Autodesk Fusion 360 part; units mm, degrees
(part 8 of 8)
equation "d1576 = ( ( ( 115 mm ) - holderFrameX / 2 ) + ( holderFrameX / 2 - holderWidth / 2 + holderHookOverlap ) ) - ( ( 115 mm ) - holderFrameX / 2 )"
equation "d1577 = ( ( ( ( ( keyRowOne ) + holderSpringY ) - holderSpringWidth / 2 ) + faceOriginV ) + ( holderSpringWidth ) ) - ( ( ( ( keyRowOne ) + holderSpringY ) - holderSpringWidth / 2 ) + faceOriginV )"
equation "d1578 = -( holderHookThickness )"
equation "d1581 = ( 115 mm ) + holderWidth / 2 + holderFit"
equation "d1582 = ( ( ( keyRowOne ) + holderSpringY ) - holderSpringWidth / 2 - 0.6 mm ) + faceOriginV"
equation "d1583 = ( ( ( 115 mm ) + holderWidth / 2 + holderFit ) + ( holderFrameX / 2 - holderWidth / 2 - holderFit + 0.1 mm ) ) - ( ( 115 mm ) + holderWidth / 2 + holderFit )"
equation "d1584 = ( ( ( ( ( keyRowOne ) + holderSpringY ) - holderSpringWidth / 2 - 0.6 mm ) + faceOriginV ) + ( 0.6 mm ) ) - ( ( ( ( keyRowOne ) + holderSpringY ) - holderSpringWidth / 2 - 0.6 mm ) + faceOriginV )"
equation "d1585 = -( holderBottomDepth + holderHookThickness - shellWall - carrierClearance - carrierThickness - 1 mm + 0.2 mm )"
equation "d1587 = ( 115 mm ) + holderWidth / 2 + holderFit"
equation "d1588 = ( ( ( keyRowOne ) + holderSpringY ) + holderSpringWidth / 2 ) + faceOriginV"
equation "d1589 = ( ( ( 115 mm ) + holderWidth / 2 + holderFit ) + ( holderFrameX / 2 - holderWidth / 2 - holderFit + 0.1 mm ) ) - ( ( 115 mm ) + holderWidth / 2 + holderFit )"
equation "d1590 = ( ( ( ( ( keyRowOne ) + holderSpringY ) + holderSpringWidth / 2 ) + faceOriginV ) + ( 0.6 mm ) ) - ( ( ( ( keyRowOne ) + holderSpringY ) + holderSpringWidth / 2 ) + faceOriginV )"
equation "d1591 = -( holderBottomDepth + holderHookThickness - shellWall - carrierClearance - carrierThickness - 1 mm + 0.2 mm )"
equation "d1593 = ( 115 mm ) + holderWidth / 2 + holderFit"
equation "d1594 = ( ( ( keyRowOne ) + holderSpringY ) - holderSpringWidth / 2 ) + faceOriginV"
equation "d1595 = ( ( ( 115 mm ) + holderWidth / 2 + holderFit ) + ( holderFrameX / 2 - 0.8 mm - holderWidth / 2 - holderFit ) ) - ( ( 115 mm ) + holderWidth / 2 + holderFit )"
equation "d1596 = ( ( ( ( ( keyRowOne ) + holderSpringY ) - holderSpringWidth / 2 ) + faceOriginV ) + ( holderSpringWidth ) ) - ( ( ( ( keyRowOne ) + holderSpringY ) - holderSpringWidth / 2 ) + faceOriginV )"
equation "d1597 = -( holderHeight + holderHookThickness + 0.2 mm )"
equation "d1599 = ( 115 mm ) + holderWidth / 2 - holderHookOverlap"
equation "d1600 = ( ( ( keyRowOne ) + holderSpringY ) - holderSpringWidth / 2 ) + faceOriginV"
equation "d1601 = ( ( ( 115 mm ) + holderWidth / 2 - holderHookOverlap ) + ( holderFrameX / 2 - holderWidth / 2 + holderHookOverlap ) ) - ( ( 115 mm ) + holderWidth / 2 - holderHookOverlap )"
equation "d1602 = ( ( ( ( ( keyRowOne ) + holderSpringY ) - holderSpringWidth / 2 ) + faceOriginV ) + ( holderSpringWidth ) ) - ( ( ( ( keyRowOne ) + holderSpringY ) - holderSpringWidth / 2 ) + faceOriginV )"
equation "d1603 = -( holderHookThickness )"
equation "d1606 = ( 115 mm ) - 11 mm"
equation "d1607 = ( ( keyRowOne ) * cos(caseTilt) + ( holderBottomDepth + holderLidGap ) * sin(caseTilt) ) - 11 mm"
equation "d1608 = ( ( ( 115 mm ) - 11 mm ) + ( 22 mm ) ) - ( ( 115 mm ) - 11 mm )"
equation "d1609 = ( ( ( ( keyRowOne ) * cos(caseTilt) + ( holderBottomDepth + holderLidGap ) * sin(caseTilt) ) - 11 mm ) + ( 22 mm ) ) - ( ( ( keyRowOne ) * cos(caseTilt) + ( holderBottomDepth + holderLidGap ) * sin(caseTilt) ) - 11 mm )"
equation "d1610 = bottomThickness"
equation "d1612 = ( 115 mm ) + ( -2.5 mm ) - 1.2 mm"
equation "d1613 = ( ( ( keyRowOne ) - 1.2 mm ) * cos(caseTilt) + ( holderBottomDepth + holderLidGap ) * sin(caseTilt) ) - 2.5 mm"
equation "d1614 = ( ( ( 115 mm ) + ( -2.5 mm ) - 1.2 mm ) + ( 2.4 mm ) ) - ( ( 115 mm ) + ( -2.5 mm ) - 1.2 mm )"
equation "d1615 = ( ( ( ( ( keyRowOne ) - 1.2 mm ) * cos(caseTilt) + ( holderBottomDepth + holderLidGap ) * sin(caseTilt) ) - 2.5 mm ) + ( 5 mm ) ) - ( ( ( ( keyRowOne ) - 1.2 mm ) * cos(caseTilt) + ( holderBottomDepth + holderLidGap ) * sin(caseTilt) ) - 2.5 mm )"
equation "d1616 = ( frontHeight + ( ( keyRowOne ) - 1.2 mm ) * sin(caseTilt) - ( holderBottomDepth + holderLidGap ) * cos(caseTilt) ) - bottomThickness - 2 mm"
equation "d1618 = ( 115 mm ) + ( -2.5 mm ) - 0.5 mm"
equation "d1619 = ( ( ( keyRowOne ) - 1.2 mm ) * cos(caseTilt) + ( holderBottomDepth + holderLidGap ) * sin(caseTilt) ) - 1.5 mm"
equation "d1620 = ( ( ( 115 mm ) + ( -2.5 mm ) - 0.5 mm ) + ( 1 mm ) ) - ( ( 115 mm ) + ( -2.5 mm ) - 0.5 mm )"
equation "d1621 = ( ( ( ( ( keyRowOne ) - 1.2 mm ) * cos(caseTilt) + ( holderBottomDepth + holderLidGap ) * sin(caseTilt) ) - 1.5 mm ) + ( 3 mm ) ) - ( ( ( ( keyRowOne ) - 1.2 mm ) * cos(caseTilt) + ( holderBottomDepth + holderLidGap ) * sin(caseTilt) ) - 1.5 mm )"
equation "d1622 = ( frontHeight + ( ( keyRowOne ) - 1.2 mm ) * sin(caseTilt) - ( holderBottomDepth + holderLidGap ) * cos(caseTilt) ) - bottomThickness + 0.5 mm"
equation "d1624 = ( ( 115 mm ) + ( -2.5 mm ) - 0.5 mm ) - 0.1 mm"
equation "d1625 = ( ( ( keyRowOne ) - 1.2 mm ) - 2 mm ) + faceOriginV"
equation "d1626 = ( ( ( ( 115 mm ) + ( -2.5 mm ) - 0.5 mm ) - 0.1 mm ) + ( 1.2 mm ) ) - ( ( ( 115 mm ) + ( -2.5 mm ) - 0.5 mm ) - 0.1 mm )"
equation "d1627 = ( ( ( ( ( keyRowOne ) - 1.2 mm ) - 2 mm ) + faceOriginV ) + ( 4 mm ) ) - ( ( ( ( keyRowOne ) - 1.2 mm ) - 2 mm ) + faceOriginV )"
equation "d1628 = rearHeight"
equation "d1630 = ( 115 mm ) + ( 2.5 mm ) - 1.2 mm"
equation "d1631 = ( ( ( keyRowOne ) - 1.2 mm ) * cos(caseTilt) + ( holderBottomDepth + holderLidGap ) * sin(caseTilt) ) - 2.5 mm"
equation "d1632 = ( ( ( 115 mm ) + ( 2.5 mm ) - 1.2 mm ) + ( 2.4 mm ) ) - ( ( 115 mm ) + ( 2.5 mm ) - 1.2 mm )"
equation "d1633 = ( ( ( ( ( keyRowOne ) - 1.2 mm ) * cos(caseTilt) + ( holderBottomDepth + holderLidGap ) * sin(caseTilt) ) - 2.5 mm ) + ( 5 mm ) ) - ( ( ( ( keyRowOne ) - 1.2 mm ) * cos(caseTilt) + ( holderBottomDepth + holderLidGap ) * sin(caseTilt) ) - 2.5 mm )"
equation "d1634 = ( frontHeight + ( ( keyRowOne ) - 1.2 mm ) * sin(caseTilt) - ( holderBottomDepth + holderLidGap ) * cos(caseTilt) ) - bottomThickness - 2 mm"
equation "d1636 = ( 115 mm ) + ( 2.5 mm ) - 0.5 mm"
equation "d1637 = ( ( ( keyRowOne ) - 1.2 mm ) * cos(caseTilt) + ( holderBottomDepth + holderLidGap ) * sin(caseTilt) ) - 1.5 mm"
equation "d1638 = ( ( ( 115 mm ) + ( 2.5 mm ) - 0.5 mm ) + ( 1 mm ) ) - ( ( 115 mm ) + ( 2.5 mm ) - 0.5 mm )"
equation "d1639 = ( ( ( ( ( keyRowOne ) - 1.2 mm ) * cos(caseTilt) + ( holderBottomDepth + holderLidGap ) * sin(caseTilt) ) - 1.5 mm ) + ( 3 mm ) ) - ( ( ( ( keyRowOne ) - 1.2 mm ) * cos(caseTilt) + ( holderBottomDepth + holderLidGap ) * sin(caseTilt) ) - 1.5 mm )"
equation "d1640 = ( frontHeight + ( ( keyRowOne ) - 1.2 mm ) * sin(caseTilt) - ( holderBottomDepth + holderLidGap ) * cos(caseTilt) ) - bottomThickness + 0.5 mm"
equation "d1642 = ( ( 115 mm ) + ( 2.5 mm ) - 0.5 mm ) - 0.1 mm"
equation "d1643 = ( ( ( keyRowOne ) - 1.2 mm ) - 2 mm ) + faceOriginV"
equation "d1644 = ( ( ( ( 115 mm ) + ( 2.5 mm ) - 0.5 mm ) - 0.1 mm ) + ( 1.2 mm ) ) - ( ( ( 115 mm ) + ( 2.5 mm ) - 0.5 mm ) - 0.1 mm )"
equation "d1645 = ( ( ( ( ( keyRowOne ) - 1.2 mm ) - 2 mm ) + faceOriginV ) + ( 4 mm ) ) - ( ( ( ( keyRowOne ) - 1.2 mm ) - 2 mm ) + faceOriginV )"
equation "d1646 = rearHeight"
equation "d1648 = ( layoutGap + keycapSize / 2 + 0 * keyPitch ) + ( -3 mm ) - 0.5 mm"
equation "d1649 = ( ( keyRowOne ) + 4 mm ) + faceOriginV"
equation "d1650 = ( ( ( layoutGap + keycapSize / 2 + 0 * keyPitch ) + ( -3 mm ) - 0.5 mm ) + ( 1 mm ) ) - ( ( layoutGap + keycapSize / 2 + 0 * keyPitch ) + ( -3 mm ) - 0.5 mm )"
equation "d1651 = ( ( ( ( keyRowOne ) + 4 mm ) + faceOriginV ) + ( holderFrameY / 2 - 4 mm ) ) - ( ( ( keyRowOne ) + 4 mm ) + faceOriginV )"
equation "d1654 = ( layoutGap + keycapSize / 2 + 0 * keyPitch ) + ( 3 mm ) - 0.5 mm"
equation "d1655 = ( ( keyRowOne ) + 4 mm ) + faceOriginV"
equation "d1656 = ( ( ( layoutGap + keycapSize / 2 + 0 * keyPitch ) + ( 3 mm ) - 0.5 mm ) + ( 1 mm ) ) - ( ( layoutGap + keycapSize / 2 + 0 * keyPitch ) + ( 3 mm ) - 0.5 mm )"
equation "d1657 = ( ( ( ( keyRowOne ) + 4 mm ) + faceOriginV ) + ( holderFrameY / 2 - 4 mm ) ) - ( ( ( keyRowOne ) + 4 mm ) + faceOriginV )"
equation "d1660 = ( layoutGap + keycapSize / 2 + 1 * keyPitch ) + ( -3 mm ) - 0.5 mm"
equation "d1661 = ( ( keyRowOne ) + 4 mm ) + faceOriginV"
equation "d1662 = ( ( ( layoutGap + keycapSize / 2 + 1 * keyPitch ) + ( -3 mm ) - 0.5 mm ) + ( 1 mm ) ) - ( ( layoutGap + keycapSize / 2 + 1 * keyPitch ) + ( -3 mm ) - 0.5 mm )"
equation "d1663 = ( ( ( ( keyRowOne ) + 4 mm ) + faceOriginV ) + ( holderFrameY / 2 - 4 mm ) ) - ( ( ( keyRowOne ) + 4 mm ) + faceOriginV )"
equation "d1666 = ( layoutGap + keycapSize / 2 + 1 * keyPitch ) + ( 3 mm ) - 0.5 mm"
equation "d1667 = ( ( keyRowOne ) + 4 mm ) + faceOriginV"
equation "d1668 = ( ( ( layoutGap + keycapSize / 2 + 1 * keyPitch ) + ( 3 mm ) - 0.5 mm ) + ( 1 mm ) ) - ( ( layoutGap + keycapSize / 2 + 1 * keyPitch ) + ( 3 mm ) - 0.5 mm )"
equation "d1669 = ( ( ( ( keyRowOne ) + 4 mm ) + faceOriginV ) + ( holderFrameY / 2 - 4 mm ) ) - ( ( ( keyRowOne ) + 4 mm ) + faceOriginV )"
equation "d1672 = ( layoutGap + keycapSize / 2 + 2 * keyPitch ) + ( -3 mm ) - 0.5 mm"
equation "d1673 = ( ( keyRowOne ) + 4 mm ) + faceOriginV"
equation "d1674 = ( ( ( layoutGap + keycapSize / 2 + 2 * keyPitch ) + ( -3 mm ) - 0.5 mm ) + ( 1 mm ) ) - ( ( layoutGap + keycapSize / 2 + 2 * keyPitch ) + ( -3 mm ) - 0.5 mm )"
equation "d1675 = ( ( ( ( keyRowOne ) + 4 mm ) + faceOriginV ) + ( holderFrameY / 2 - 4 mm ) ) - ( ( ( keyRowOne ) + 4 mm ) + faceOriginV )"
equation "d1678 = ( layoutGap + keycapSize / 2 + 2 * keyPitch ) + ( 3 mm ) - 0.5 mm"
equation "d1679 = ( ( keyRowOne ) + 4 mm ) + faceOriginV"
equation "d1680 = ( ( ( layoutGap + keycapSize / 2 + 2 * keyPitch ) + ( 3 mm ) - 0.5 mm ) + ( 1 mm ) ) - ( ( layoutGap + keycapSize / 2 + 2 * keyPitch ) + ( 3 mm ) - 0.5 mm )"
equation "d1681 = ( ( ( ( keyRowOne ) + 4 mm ) + faceOriginV ) + ( holderFrameY / 2 - 4 mm ) ) - ( ( ( keyRowOne ) + 4 mm ) + faceOriginV )"
equation "d1684 = ( layoutGap + keycapSize / 2 + 0 * keyPitch ) + ( -3 mm ) - 0.5 mm"
equation "d1685 = ( ( keyRowTwo ) + 4 mm ) + faceOriginV"
equation "d1686 = ( ( ( layoutGap + keycapSize / 2 + 0 * keyPitch ) + ( -3 mm ) - 0.5 mm ) + ( 1 mm ) ) - ( ( layoutGap + keycapSize / 2 + 0 * keyPitch ) + ( -3 mm ) - 0.5 mm )"
equation "d1687 = ( ( ( ( keyRowTwo ) + 4 mm ) + faceOriginV ) + ( holderFrameY / 2 - 4 mm ) ) - ( ( ( keyRowTwo ) + 4 mm ) + faceOriginV )"
equation "d1690 = ( layoutGap + keycapSize / 2 + 0 * keyPitch ) + ( 3 mm ) - 0.5 mm"
equation "d1691 = ( ( keyRowTwo ) + 4 mm ) + faceOriginV"
equation "d1692 = ( ( ( layoutGap + keycapSize / 2 + 0 * keyPitch ) + ( 3 mm ) - 0.5 mm ) + ( 1 mm ) ) - ( ( layoutGap + keycapSize / 2 + 0 * keyPitch ) + ( 3 mm ) - 0.5 mm )"
equation "d1693 = ( ( ( ( keyRowTwo ) + 4 mm ) + faceOriginV ) + ( holderFrameY / 2 - 4 mm ) ) - ( ( ( keyRowTwo ) + 4 mm ) + faceOriginV )"
equation "d1696 = ( layoutGap + keycapSize / 2 + 1 * keyPitch ) + ( -3 mm ) - 0.5 mm"
equation "d1697 = ( ( keyRowTwo ) + 4 mm ) + faceOriginV"
equation "d1698 = ( ( ( layoutGap + keycapSize / 2 + 1 * keyPitch ) + ( -3 mm ) - 0.5 mm ) + ( 1 mm ) ) - ( ( layoutGap + keycapSize / 2 + 1 * keyPitch ) + ( -3 mm ) - 0.5 mm )"
equation "d1699 = ( ( ( ( keyRowTwo ) + 4 mm ) + faceOriginV ) + ( holderFrameY / 2 - 4 mm ) ) - ( ( ( keyRowTwo ) + 4 mm ) + faceOriginV )"
equation "d1702 = ( layoutGap + keycapSize / 2 + 1 * keyPitch ) + ( 3 mm ) - 0.5 mm"
equation "d1703 = ( ( keyRowTwo ) + 4 mm ) + faceOriginV"
equation "d1704 = ( ( ( layoutGap + keycapSize / 2 + 1 * keyPitch ) + ( 3 mm ) - 0.5 mm ) + ( 1 mm ) ) - ( ( layoutGap + keycapSize / 2 + 1 * keyPitch ) + ( 3 mm ) - 0.5 mm )"
equation "d1705 = ( ( ( ( keyRowTwo ) + 4 mm ) + faceOriginV ) + ( holderFrameY / 2 - 4 mm ) ) - ( ( ( keyRowTwo ) + 4 mm ) + faceOriginV )"
equation "d1708 = ( layoutGap + keycapSize / 2 + 2 * keyPitch ) + ( -3 mm ) - 0.5 mm"
equation "d1709 = ( ( keyRowTwo ) + 4 mm ) + faceOriginV"
equation "d1710 = ( ( ( layoutGap + keycapSize / 2 + 2 * keyPitch ) + ( -3 mm ) - 0.5 mm ) + ( 1 mm ) ) - ( ( layoutGap + keycapSize / 2 + 2 * keyPitch ) + ( -3 mm ) - 0.5 mm )"
equation "d1711 = ( ( ( ( keyRowTwo ) + 4 mm ) + faceOriginV ) + ( holderFrameY / 2 - 4 mm ) ) - ( ( ( keyRowTwo ) + 4 mm ) + faceOriginV )"
equation "d1714 = ( layoutGap + keycapSize / 2 + 2 * keyPitch ) + ( 3 mm ) - 0.5 mm"
equation "d1715 = ( ( keyRowTwo ) + 4 mm ) + faceOriginV"
equation "d1716 = ( ( ( layoutGap + keycapSize / 2 + 2 * keyPitch ) + ( 3 mm ) - 0.5 mm ) + ( 1 mm ) ) - ( ( layoutGap + keycapSize / 2 + 2 * keyPitch ) + ( 3 mm ) - 0.5 mm )"
equation "d1717 = ( ( ( ( keyRowTwo ) + 4 mm ) + faceOriginV ) + ( holderFrameY / 2 - 4 mm ) ) - ( ( ( keyRowTwo ) + 4 mm ) + faceOriginV )"
equation "d1720 = ( 115 mm ) + ( -3 mm ) - 0.5 mm"
equation "d1721 = ( ( keyRowOne ) + 4 mm ) + faceOriginV"
equation "d1722 = ( ( ( 115 mm ) + ( -3 mm ) - 0.5 mm ) + ( 1 mm ) ) - ( ( 115 mm ) + ( -3 mm ) - 0.5 mm )"
equation "d1723 = ( ( ( ( keyRowOne ) + 4 mm ) + faceOriginV ) + ( holderFrameY / 2 - 4 mm ) ) - ( ( ( keyRowOne ) + 4 mm ) + faceOriginV )"
equation "d1726 = ( 115 mm ) + ( 3 mm ) - 0.5 mm"
equation "d1727 = ( ( keyRowOne ) + 4 mm ) + faceOriginV"
equation "d1728 = ( ( ( 115 mm ) + ( 3 mm ) - 0.5 mm ) + ( 1 mm ) ) - ( ( 115 mm ) + ( 3 mm ) - 0.5 mm )"
equation "d1729 = ( ( ( ( keyRowOne ) + 4 mm ) + faceOriginV ) + ( holderFrameY / 2 - 4 mm ) ) - ( ( ( keyRowOne ) + 4 mm ) + faceOriginV )"
equation "d1734 = ( layoutGap + keycapSize / 2 + 0 * keyPitch ) - holderFrameX / 2 - 0.1 mm"
equation "d1735 = ( ( keyRowOne ) - 5.1 mm ) + faceOriginV"
equation "d1736 = ( ( ( layoutGap + keycapSize / 2 + 0 * keyPitch ) - holderFrameX / 2 - 0.1 mm ) + ( holderFrameX / 2 - holderWidth / 2 + 0.1 mm ) ) - ( ( layoutGap + keycapSize / 2 + 0 * keyPitch ) - holderFrameX / 2 - 0.1 mm )"
equation "d1737 = ( ( ( ( keyRowOne ) - 5.1 mm ) + faceOriginV ) + ( 7.8 mm ) ) - ( ( ( keyRowOne ) - 5.1 mm ) + faceOriginV )"
equation "d1738 = -( holderHeight + holderHookThickness - 1.2 mm + 0.2 mm )"
equation "d1740 = ( layoutGap + keycapSize / 2 + 0 * keyPitch ) + holderWidth / 2"
equation "d1741 = ( ( keyRowOne ) - 5.1 mm ) + faceOriginV"
equation "d1742 = ( ( ( layoutGap + keycapSize / 2 + 0 * keyPitch ) + holderWidth / 2 ) + ( holderFrameX / 2 - holderWidth / 2 + 0.1 mm ) ) - ( ( layoutGap + keycapSize / 2 + 0 * keyPitch ) + holderWidth / 2 )"
equation "d1743 = ( ( ( ( keyRowOne ) - 5.1 mm ) + faceOriginV ) + ( 7.8 mm ) ) - ( ( ( keyRowOne ) - 5.1 mm ) + faceOriginV )"
equation "d1744 = -( holderHeight + holderHookThickness - 1.2 mm + 0.2 mm )"
equation "d1746 = ( layoutGap + keycapSize / 2 + 1 * keyPitch ) - holderFrameX / 2 - 0.1 mm"
equation "d1747 = ( ( keyRowOne ) - 5.1 mm ) + faceOriginV"
equation "d1748 = ( ( ( layoutGap + keycapSize / 2 + 1 * keyPitch ) - holderFrameX / 2 - 0.1 mm ) + ( holderFrameX / 2 - holderWidth / 2 + 0.1 mm ) ) - ( ( layoutGap + keycapSize / 2 + 1 * keyPitch ) - holderFrameX / 2 - 0.1 mm )"
equation "d1749 = ( ( ( ( keyRowOne ) - 5.1 mm ) + faceOriginV ) + ( 7.8 mm ) ) - ( ( ( keyRowOne ) - 5.1 mm ) + faceOriginV )"
equation "d1750 = -( holderHeight + holderHookThickness - 1.2 mm + 0.2 mm )"
equation "d1752 = ( layoutGap + keycapSize / 2 + 1 * keyPitch ) + holderWidth / 2"
equation "d1753 = ( ( keyRowOne ) - 5.1 mm ) + faceOriginV"
equation "d1754 = ( ( ( layoutGap + keycapSize / 2 + 1 * keyPitch ) + holderWidth / 2 ) + ( holderFrameX / 2 - holderWidth / 2 + 0.1 mm ) ) - ( ( layoutGap + keycapSize / 2 + 1 * keyPitch ) + holderWidth / 2 )"
equation "d1755 = ( ( ( ( keyRowOne ) - 5.1 mm ) + faceOriginV ) + ( 7.8 mm ) ) - ( ( ( keyRowOne ) - 5.1 mm ) + faceOriginV )"
equation "d1756 = -( holderHeight + holderHookThickness - 1.2 mm + 0.2 mm )"
equation "d1758 = ( layoutGap + keycapSize / 2 + 2 * keyPitch ) - holderFrameX / 2 - 0.1 mm"
equation "d1759 = ( ( keyRowOne ) - 5.1 mm ) + faceOriginV"
equation "d1760 = ( ( ( layoutGap + keycapSize / 2 + 2 * keyPitch ) - holderFrameX / 2 - 0.1 mm ) + ( holderFrameX / 2 - holderWidth / 2 + 0.1 mm ) ) - ( ( layoutGap + keycapSize / 2 + 2 * keyPitch ) - holderFrameX / 2 - 0.1 mm )"
equation "d1761 = ( ( ( ( keyRowOne ) - 5.1 mm ) + faceOriginV ) + ( 7.8 mm ) ) - ( ( ( keyRowOne ) - 5.1 mm ) + faceOriginV )"
equation "d1762 = -( holderHeight + holderHookThickness - 1.2 mm + 0.2 mm )"
equation "d1764 = ( layoutGap + keycapSize / 2 + 2 * keyPitch ) + holderWidth / 2"
equation "d1765 = ( ( keyRowOne ) - 5.1 mm ) + faceOriginV"
equation "d1766 = ( ( ( layoutGap + keycapSize / 2 + 2 * keyPitch ) + holderWidth / 2 ) + ( holderFrameX / 2 - holderWidth / 2 + 0.1 mm ) ) - ( ( layoutGap + keycapSize / 2 + 2 * keyPitch ) + holderWidth / 2 )"
equation "d1767 = ( ( ( ( keyRowOne ) - 5.1 mm ) + faceOriginV ) + ( 7.8 mm ) ) - ( ( ( keyRowOne ) - 5.1 mm ) + faceOriginV )"
equation "d1768 = -( holderHeight + holderHookThickness - 1.2 mm + 0.2 mm )"
equation "d1770 = ( layoutGap + keycapSize / 2 + 0 * keyPitch ) - holderFrameX / 2 - 0.1 mm"
equation "d1771 = ( ( keyRowTwo ) - 5.1 mm ) + faceOriginV"
equation "d1772 = ( ( ( layoutGap + keycapSize / 2 + 0 * keyPitch ) - holderFrameX / 2 - 0.1 mm ) + ( holderFrameX / 2 - holderWidth / 2 + 0.1 mm ) ) - ( ( layoutGap + keycapSize / 2 + 0 * keyPitch ) - holderFrameX / 2 - 0.1 mm )"
equation "d1773 = ( ( ( ( keyRowTwo ) - 5.1 mm ) + faceOriginV ) + ( 7.8 mm ) ) - ( ( ( keyRowTwo ) - 5.1 mm ) + faceOriginV )"
equation "d1774 = -( holderHeight + holderHookThickness - 1.2 mm + 0.2 mm )"
equation "d1776 = ( layoutGap + keycapSize / 2 + 0 * keyPitch ) + holderWidth / 2"
equation "d1777 = ( ( keyRowTwo ) - 5.1 mm ) + faceOriginV"
equation "d1778 = ( ( ( layoutGap + keycapSize / 2 + 0 * keyPitch ) + holderWidth / 2 ) + ( holderFrameX / 2 - holderWidth / 2 + 0.1 mm ) ) - ( ( layoutGap + keycapSize / 2 + 0 * keyPitch ) + holderWidth / 2 )"
equation "d1779 = ( ( ( ( keyRowTwo ) - 5.1 mm ) + faceOriginV ) + ( 7.8 mm ) ) - ( ( ( keyRowTwo ) - 5.1 mm ) + faceOriginV )"
equation "d1780 = -( holderHeight + holderHookThickness - 1.2 mm + 0.2 mm )"
equation "d1782 = ( layoutGap + keycapSize / 2 + 1 * keyPitch ) - holderFrameX / 2 - 0.1 mm"
equation "d1783 = ( ( keyRowTwo ) - 5.1 mm ) + faceOriginV"
equation "d1784 = ( ( ( layoutGap + keycapSize / 2 + 1 * keyPitch ) - holderFrameX / 2 - 0.1 mm ) + ( holderFrameX / 2 - holderWidth / 2 + 0.1 mm ) ) - ( ( layoutGap + keycapSize / 2 + 1 * keyPitch ) - holderFrameX / 2 - 0.1 mm )"
equation "d1785 = ( ( ( ( keyRowTwo ) - 5.1 mm ) + faceOriginV ) + ( 7.8 mm ) ) - ( ( ( keyRowTwo ) - 5.1 mm ) + faceOriginV )"
equation "d1786 = -( holderHeight + holderHookThickness - 1.2 mm + 0.2 mm )"
equation "d1788 = ( layoutGap + keycapSize / 2 + 1 * keyPitch ) + holderWidth / 2"
equation "d1789 = ( ( keyRowTwo ) - 5.1 mm ) + faceOriginV"
equation "d1790 = ( ( ( layoutGap + keycapSize / 2 + 1 * keyPitch ) + holderWidth / 2 ) + ( holderFrameX / 2 - holderWidth / 2 + 0.1 mm ) ) - ( ( layoutGap + keycapSize / 2 + 1 * keyPitch ) + holderWidth / 2 )"
equation "d1791 = ( ( ( ( keyRowTwo ) - 5.1 mm ) + faceOriginV ) + ( 7.8 mm ) ) - ( ( ( keyRowTwo ) - 5.1 mm ) + faceOriginV )"
equation "d1792 = -( holderHeight + holderHookThickness - 1.2 mm + 0.2 mm )"
equation "d1794 = ( layoutGap + keycapSize / 2 + 2 * keyPitch ) - holderFrameX / 2 - 0.1 mm"
equation "d1795 = ( ( keyRowTwo ) - 5.1 mm ) + faceOriginV"
equation "d1796 = ( ( ( layoutGap + keycapSize / 2 + 2 * keyPitch ) - holderFrameX / 2 - 0.1 mm ) + ( holderFrameX / 2 - holderWidth / 2 + 0.1 mm ) ) - ( ( layoutGap + keycapSize / 2 + 2 * keyPitch ) - holderFrameX / 2 - 0.1 mm )"
equation "d1797 = ( ( ( ( keyRowTwo ) - 5.1 mm ) + faceOriginV ) + ( 7.8 mm ) ) - ( ( ( keyRowTwo ) - 5.1 mm ) + faceOriginV )"
equation "d1798 = -( holderHeight + holderHookThickness - 1.2 mm + 0.2 mm )"
equation "d1800 = ( layoutGap + keycapSize / 2 + 2 * keyPitch ) + holderWidth / 2"
equation "d1801 = ( ( keyRowTwo ) - 5.1 mm ) + faceOriginV"
equation "d1802 = ( ( ( layoutGap + keycapSize / 2 + 2 * keyPitch ) + holderWidth / 2 ) + ( holderFrameX / 2 - holderWidth / 2 + 0.1 mm ) ) - ( ( layoutGap + keycapSize / 2 + 2 * keyPitch ) + holderWidth / 2 )"
equation "d1803 = ( ( ( ( keyRowTwo ) - 5.1 mm ) + faceOriginV ) + ( 7.8 mm ) ) - ( ( ( keyRowTwo ) - 5.1 mm ) + faceOriginV )"
equation "d1804 = -( holderHeight + holderHookThickness - 1.2 mm + 0.2 mm )"
equation "d1806 = ( 115 mm ) - holderFrameX / 2 - 0.1 mm"
equation "d1807 = ( ( keyRowOne ) - 5.1 mm ) + faceOriginV"
equation "d1808 = ( ( ( 115 mm ) - holderFrameX / 2 - 0.1 mm ) + ( holderFrameX / 2 - holderWidth / 2 + 0.1 mm ) ) - ( ( 115 mm ) - holderFrameX / 2 - 0.1 mm )"
equation "d1809 = ( ( ( ( keyRowOne ) - 5.1 mm ) + faceOriginV ) + ( 7.8 mm ) ) - ( ( ( keyRowOne ) - 5.1 mm ) + faceOriginV )"
equation "d1810 = -( holderHeight + holderHookThickness - 1.2 mm + 0.2 mm )"
equation "d1812 = ( 115 mm ) + holderWidth / 2"
equation "d1813 = ( ( keyRowOne ) - 5.1 mm ) + faceOriginV"
equation "d1814 = ( ( ( 115 mm ) + holderWidth / 2 ) + ( holderFrameX / 2 - holderWidth / 2 + 0.1 mm ) ) - ( ( 115 mm ) + holderWidth / 2 )"
equation "d1815 = ( ( ( ( keyRowOne ) - 5.1 mm ) + faceOriginV ) + ( 7.8 mm ) ) - ( ( ( keyRowOne ) - 5.1 mm ) + faceOriginV )"
equation "d1816 = -( holderHeight + holderHookThickness - 1.2 mm + 0.2 mm )"
named bodies: "UpperShell_Draft", "MiddleCarrier_Draft", "BottomCover_Draft", "Diffuser_Draft", "SwitchFitCoupon_Trial", "LidSupportCoupon_Trial"
